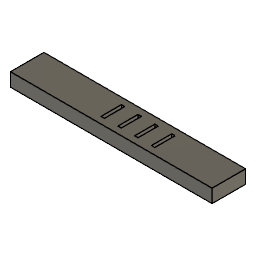
symmetric_pattern (Autodesk Fusion 360 design; units mm, degrees)
Autodesk Fusion 360 part; units mm, degrees
sketch "Sketch1" plane through (0, 0, 0) normal (0, 0, 1) x (1, 0, 0)
  line L0 (-30, 0) -> (30, 0)
  line L1 (30, 0) -> (30, 10)
  line L2 (30, 10) -> (-30, 10)
  line L3 (-30, 10) -> (-30, 0)
extrude "Extrude1" add sketch "Sketch1" along normal blind 4
sketch "Sketch2" plane through (0, 0, 4) normal (0, 0, 1) x (1, 0, 0)
  line L0 (-30, 10) -> (-30, 0)
  line L1 (-30, 0) -> (30, 0)
  line L2 (30, 0) -> (30, 10)
  line L3 (30, 10) -> (-30, 10)
  line L4 (0, 2) -> (1, 2)
  line L5 (1, 2) -> (1, 8)
  line L6 (1, 8) -> (0, 8)
  line L7 (0, 8) -> (0, 2)
extrude "Extrude2" cut sketch "Sketch2" against normal blind 1 contours L4 L5 L6 L7
pattern_linear "R-Pattern1" count 4 spacing 5 along (1, 0, 0) both ways of "Extrude2"
